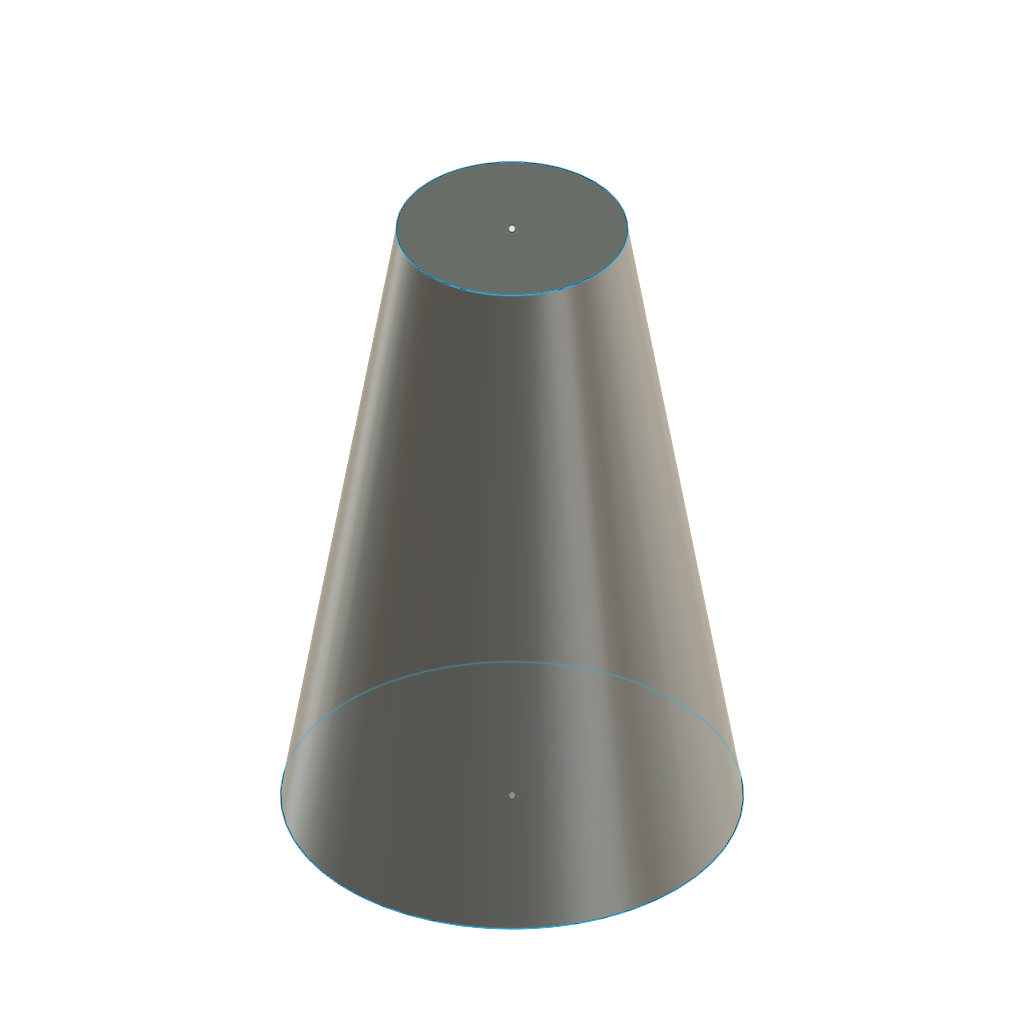
LoftCircles (Autodesk Fusion 360 design; units mm, degrees)
part number: 2026-11-12-20-32-23-940
Autodesk Fusion 360 part; units mm, degrees
sketch "Loft base" plane through (0, 0, 0) normal (0, 0, 1) x (1, 0, 0)
  circle A0 centre (0, 0) radius 10
ref_plane "WorkPlane1" through (0, 0, 30) normal (0, 0, 1) x (1, 0, 0)
sketch "Loft top" plane through (0, 0, 30) normal (0, 0, 1) x (1, 0, 0)
  circle A0 centre (0, 0) radius 5
loft "Cone loft" add profiles "Loft base", "Loft top" section 1 section 2
